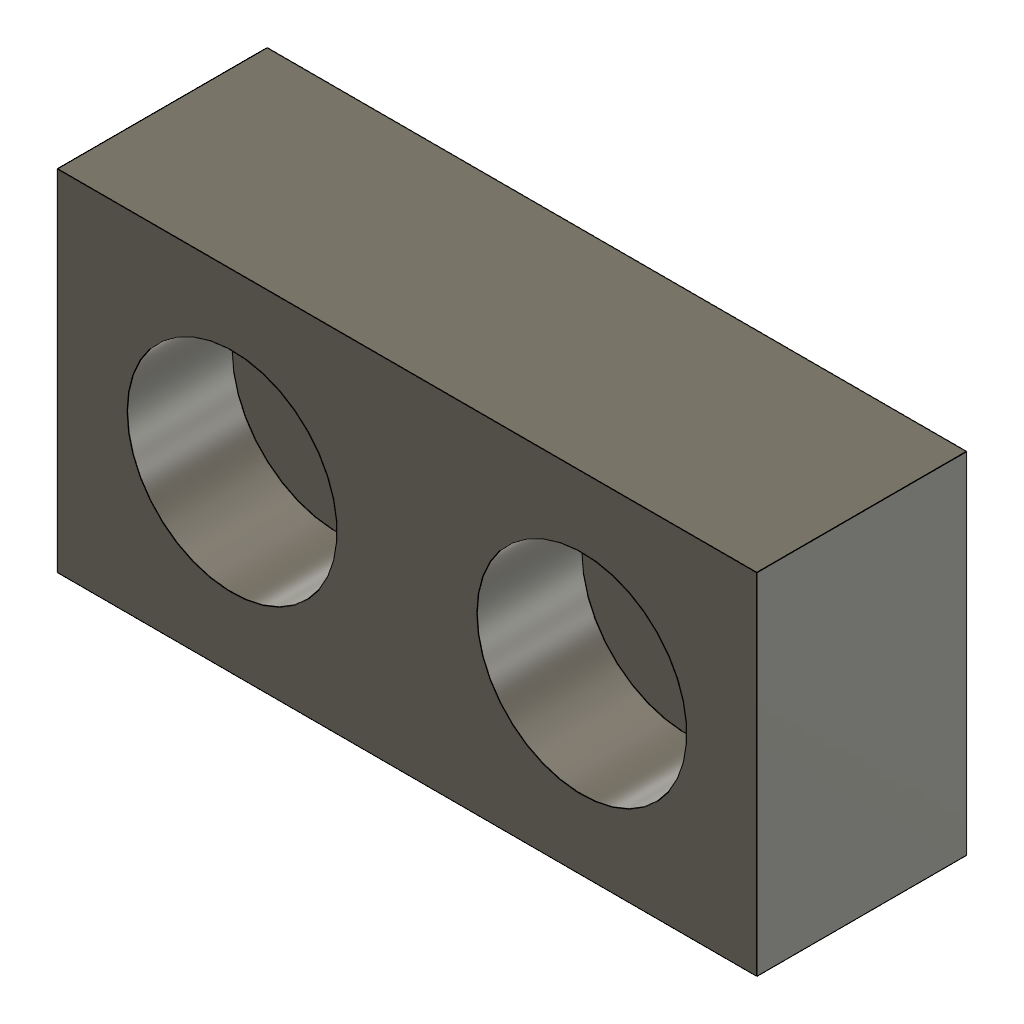
cut_from_top_face (Autodesk Fusion 360 design; units mm, degrees)
part number: 2026-11-10-15-06-42-362
Autodesk Fusion 360 part; units mm, degrees
sketch "Sketch1" plane through (0, 0, 0) normal (0, 0, 1) x (1, 0, 0)
  line L0 (0, 0) -> (20, 0)
  line L1 (20, 0) -> (20, 10)
  line L2 (20, 10) -> (0, 10)
  line L3 (0, 10) -> (0, 0)
extrude "Extrude1" add sketch "Sketch1" along normal blind 6
sketch "Sketch2" plane through (0, 0, 0) normal (0, 0, 1) x (1, 0, 0)
  circle A0 centre (5, 5) radius 3
  circle A1 centre (15, 5) radius 3
extrude "Extrude2" cut sketch "Sketch2" against normal blind 3 from surface at 6
